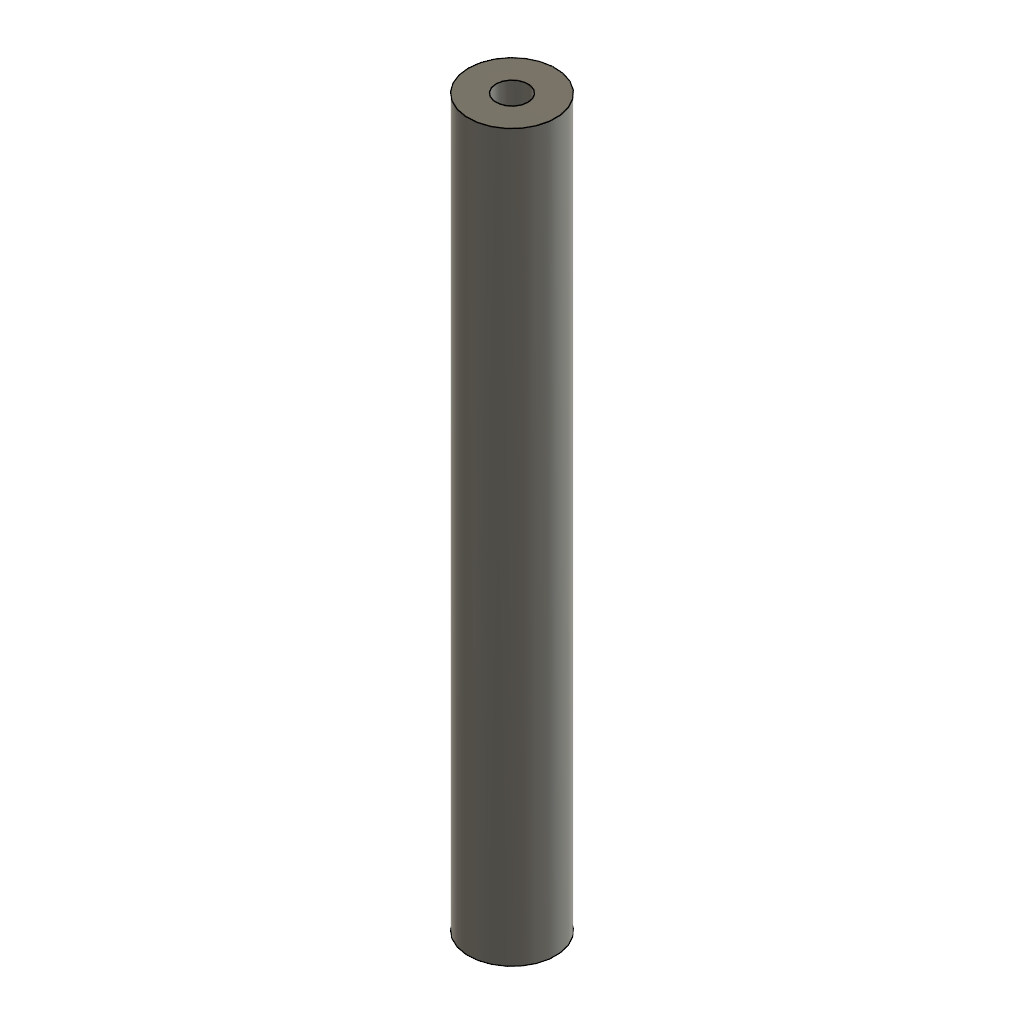
02-04_서포트너트 (Autodesk Fusion 360 design; units mm, degrees)
Autodesk Fusion 360 part; units mm, degrees
sketch "스케치1" plane through (0, 0, 0) normal (0, 1, 0) x (1, 0, 0)
  circle A0 centre (0, 0) radius 3
  dimension "d1" = 6
  constraint coincident A0.centre origin
  measures "d1" diameter of A0
extrude "돌출1" add sketch "스케치1" along normal blind 50
sketch "스케치2" plane through (0, 0, 0) normal (0, -1, 0) x (1, 0, 0)
  circle A0 centre (0, 0) radius 3
  circle A1 centre (0, 0) radius 1.1
  dimension "d4" = 2.2
  constraint coincident A0.centre A1.centre
  measures "d4" diameter of A1
extrude "돌출2" cut sketch "스케치2" against normal blind 10 contours A1
sketch "스케치3" plane through (0, 50, 0) normal (0, 1, 0) x (-1, 0, 0)
  circle A0 centre (0, 0) radius 3
  circle A1 centre (0, 0) radius 1.1
  dimension "d7" = 2.2
  constraint coincident A0.centre A1.centre
  measures "d7" diameter of A1
extrude "돌출3" cut sketch "스케치3" against normal blind 10 contours A1
